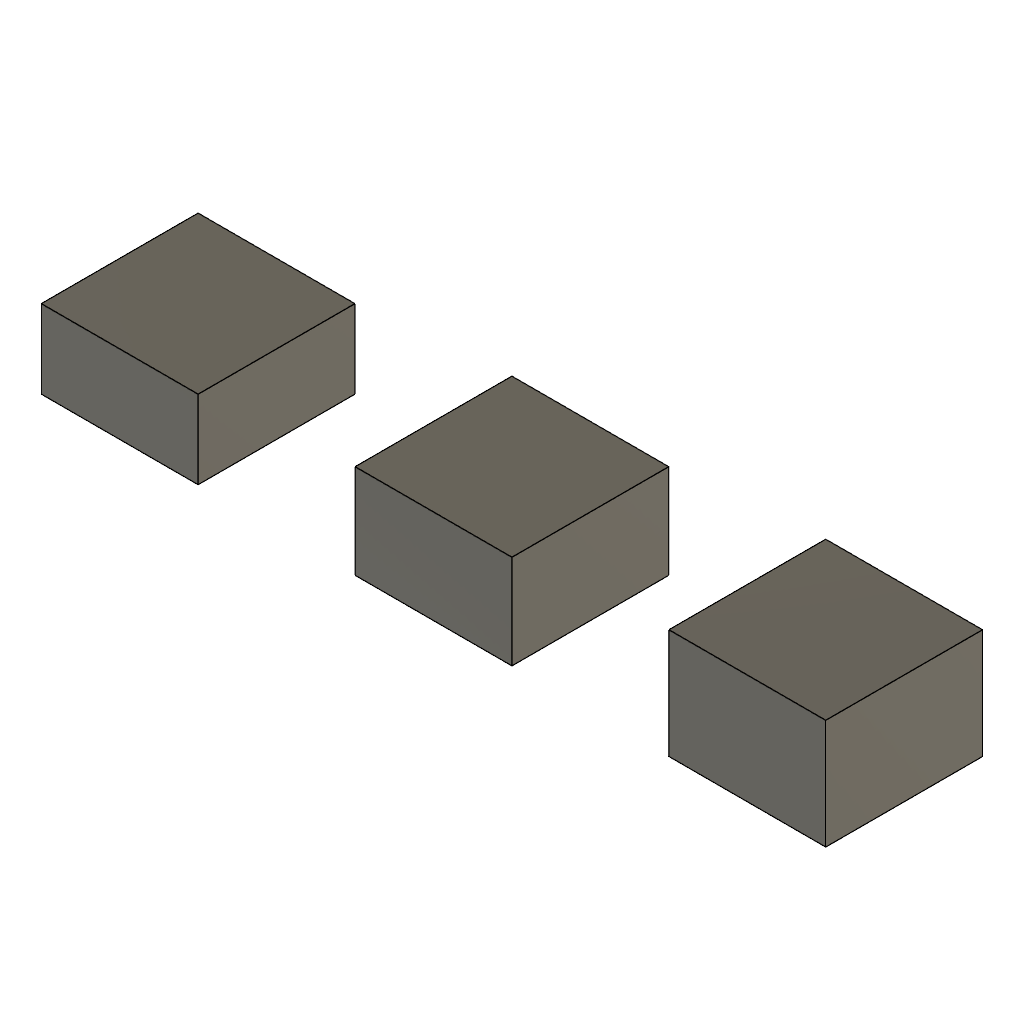
copy_paste_three_bodies (Autodesk Fusion 360 design; units mm, degrees)
Autodesk Fusion 360 part; units mm, degrees
sketch "Sketch1" plane through (0, 0, 0) normal (0, 0, 1) x (1, 0, 0) in component "A"
  line L0 (0, 0) -> (10, 0)
  line L1 (10, 0) -> (10, 10)
  line L2 (10, 10) -> (0, 10)
  line L3 (0, 10) -> (0, 0)
extrude "Extrude1" add sketch "Sketch1" along normal blind 5 makes body 1 in component "A"
sketch "Sketch2" plane through (0, 0, 0) normal (0, 0, 1) x (1, 0, 0) in component "A"
  line L0 (20, 0) -> (30, 0)
  line L1 (30, 0) -> (30, 10)
  line L2 (30, 10) -> (20, 10)
  line L3 (20, 10) -> (20, 0)
extrude "Extrude2" add sketch "Sketch2" along normal blind 6 separate body makes body 2 in component "A"
sketch "Sketch3" plane through (0, 0, 0) normal (0, 0, 1) x (1, 0, 0) in component "A"
  line L0 (40, 0) -> (50, 0)
  line L1 (50, 0) -> (50, 10)
  line L2 (50, 10) -> (40, 10)
  line L3 (40, 10) -> (40, 0)
extrude "Extrude3" add sketch "Sketch3" along normal blind 7 separate body makes body 3 in component "A"
copy_body "CopyPasteBodies1" bodies 1 2 3 body 1 seen with x (1, 0, 0) y (0, 1, 0) z (0, 0, 1) at (0, -30, 0) body 2 seen with x (1, 0, 0) y (0, 1, 0) z (0, 0, 1) at (0, -30, 0) body 3 seen with x (1, 0, 0) y (0, 1, 0) z (0, 0, 1) at (0, -30, 0) makes body 4 makes body 5 makes body 6 in component "Target"
component "A" placed x (1, 0, 0) y (0, 1, 0) z (0, 0, 1) at (0, 0, 0)
component "Target" placed x (1, 0, 0) y (0, 1, 0) z (0, 0, 1) at (0, 30, 0)
